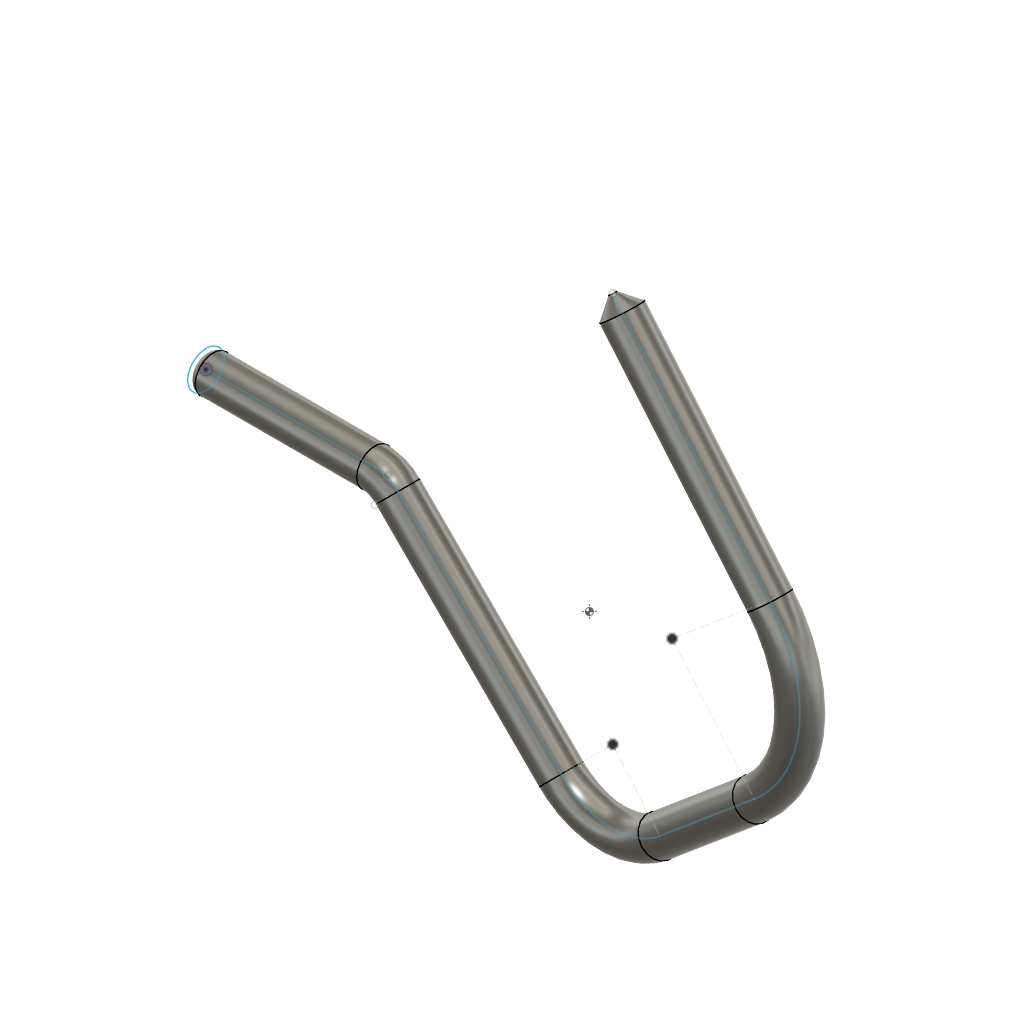
ST01M01D, Hook (Autodesk Fusion 360 design; units mm, degrees)
Autodesk Fusion 360 part; units mm, degrees
form "Form1" [no effect]
sketch "Rod" plane through (0, 0, 0) normal (1, 0, 0) x (0, 0, -1)
  circle A0 centre (0, 0) radius 3.175
  dimension "d7" = 6.35
  constraint coincident A0.centre origin
  measures "d7" diameter of A0
sketch "sketch 172" plane through (0, 0, 0) normal (0, 0, 1) x (1, 0, 0)
  line L0 (0, 0) -> (29.3828, 0)
  line L1 (33.4239, -1.6739) -> (61.8317, -30.0817)
  line L2 (98.1667, 14.286) -> (70.812, 46.8861)
  arc A0 (33.4239, -1.6739) -> (29.3828, 0) centre (29.3828, -5.715) ccw
  arc A1 (95.4274, -17.0253) -> (98.1667, 14.286) centre (81.1414, 0) ccw
  line L3 (81.1414, 0) -> (95.4274, -17.0253) construction
  line L4 (81.1414, 0) -> (98.1667, 14.286) construction
  line L5 (95.4274, -17.0253) -> (78.9754, -30.8302)
  arc A2 (61.8317, -30.0817) -> (78.9754, -30.8302) centre (70.812, -21.1014) ccw
  line L6 (70.812, -21.1014) -> (61.8317, -30.0817) construction
  line L7 (70.812, -21.1014) -> (78.9754, -30.8302) construction
  constraint coincident L0.start origin
  constraint horizontal L0
  constraint tangent L0 A0
  constraint tangent L1 A0
  constraint coincident L0 A1.centre
  constraint tangent A1 L5
  constraint tangent L2 A1
  constraint tangent L5 A2
  constraint tangent L1 A2
  constraint vertical L2.end A2.centre
sweep "Sweep1" add profiles "Rod" path "sketch 172" along L0 A0 L1 A2 L5 A1 L2 section 1
fillet "Fillet3" radius 1.27 1 edges at (0, -1.1481, 2.9601)
chamfer "Chamfer1" distance 2.54 angle 45 1 edges at (71.6915, 47.6241, 2.9601) tangent chain off
